Autodesk Fusion 360 part; units mm, degrees
(part 5 of 5)
sketch "草图7" plane through (0, 0, 4.4) normal (0, 0, 1) x (1, 0, 0) in component "03_可换镜像凹纹压片"
  line L0 (-23.5783, -0.5788) -> (-23.3448, -1.1469)
  line L1 (-23.3448, -1.1469) -> (-22.9926, -1.696)
  line L2 (-22.9926, -1.696) -> (-22.5708, -2.223)
  line L3 (-22.5708, -2.223) -> (-22.1372, -2.7304)
  line L4 (-22.1372, -2.7304) -> (-21.7491, -3.2262)
  line L5 (-21.7491, -3.2262) -> (-21.454, -3.7226)
  line L6 (-21.454, -3.7226) -> (-21.283, -4.2335)
  line L7 (-21.283, -4.2335) -> (-21.2455, -4.7708)
  line L8 (-21.2455, -4.7708) -> (-21.3281, -5.3424)
  line L9 (-21.3281, -5.3424) -> (-21.497, -5.949)
  line L10 (-21.497, -5.949) -> (-21.7034, -6.5837)
  line L11 (-21.7034, -6.5837) -> (-21.8914, -7.2319)
  line L12 (-21.8914, -7.2319) -> (-22.0067, -7.8741)
  line L13 (-22.0067, -7.8741) -> (-22.005, -8.4883)
  line L14 (-22.005, -8.4883) -> (-21.859, -9.0543)
  line L15 (-21.859, -9.0543) -> (-21.562, -9.5578)
  line L16 (-21.562, -9.5578) -> (-21.1289, -9.9932)
  line L17 (-21.1289, -9.9932) -> (-20.5933, -10.3658)
  line L18 (-20.5933, -10.3658) -> (-20.002, -10.6913)
  line L19 (-20.002, -10.6913) -> (-19.4073, -10.9941)
  line L20 (-19.4073, -10.9941) -> (-18.8589, -11.3036)
  line L21 (-18.8589, -11.3036) -> (-18.3963, -11.6494)
  line L22 (-18.3963, -11.6494) -> (-18.0429, -12.0559)
  line L23 (-18.0429, -12.0559) -> (-17.8026, -12.538)
  line L24 (-17.8026, -12.538) -> (-17.6602, -13.0977)
  line L25 (-17.6602, -13.0977) -> (-17.584, -13.7227)
  line L26 (-17.584, -13.7227) -> (-17.5319, -14.388)
  line L27 (-17.5319, -14.388) -> (-17.4575, -15.0589)
  line L28 (-17.4575, -15.0589) -> (-17.3182, -15.6963)
  line L29 (-17.3182, -15.6963) -> (-17.0817, -16.2631)
  line L30 (-17.0817, -16.2631) -> (-16.7301, -16.7301)
  line L31 (-16.7301, -16.7301) -> (-16.2631, -17.0817)
  line L32 (-16.2631, -17.0817) -> (-15.6963, -17.3182)
  line L33 (-15.6963, -17.3182) -> (-15.0589, -17.4575)
  line L34 (-15.0589, -17.4575) -> (-14.388, -17.5319)
  line L35 (-14.388, -17.5319) -> (-13.7227, -17.584)
  line L36 (-13.7227, -17.584) -> (-13.0977, -17.6602)
  line L37 (-13.0977, -17.6602) -> (-12.538, -17.8026)
  line L38 (-12.538, -17.8026) -> (-12.0559, -18.0429)
  line L39 (-12.0559, -18.0429) -> (-11.6494, -18.3963)
  line L40 (-11.6494, -18.3963) -> (-11.3036, -18.8589)
  line L41 (-11.3036, -18.8589) -> (-10.9941, -19.4073)
  line L42 (-10.9941, -19.4073) -> (-10.6913, -20.002)
  line L43 (-10.6913, -20.002) -> (-10.3658, -20.5933)
  line L44 (-10.3658, -20.5933) -> (-9.9932, -21.1289)
  line L45 (-9.9932, -21.1289) -> (-9.5578, -21.562)
  line L46 (-9.5578, -21.562) -> (-9.0543, -21.859)
  line L47 (-9.0543, -21.859) -> (-8.4883, -22.005)
  line L48 (-8.4883, -22.005) -> (-7.8741, -22.0067)
  line L49 (-7.8741, -22.0067) -> (-7.2319, -21.8914)
  line L50 (-7.2319, -21.8914) -> (-6.5837, -21.7034)
  line L51 (-6.5837, -21.7034) -> (-5.949, -21.497)
  line L52 (-5.949, -21.497) -> (-5.3424, -21.3281)
  line L53 (-5.3424, -21.3281) -> (-4.7708, -21.2455)
  line L54 (-4.7708, -21.2455) -> (-4.2335, -21.283)
  line L55 (-4.2335, -21.283) -> (-3.7226, -21.454)
  line L56 (-3.7226, -21.454) -> (-3.2262, -21.7491)
  line L57 (-3.2262, -21.7491) -> (-2.7304, -22.1372)
  line L58 (-2.7304, -22.1372) -> (-2.223, -22.5708)
  line L59 (-2.223, -22.5708) -> (-1.696, -22.9926)
  line L60 (-1.696, -22.9926) -> (-1.1469, -23.3448)
  line L61 (-1.1469, -23.3448) -> (-0.5788, -23.5783)
  line L62 (-0.5788, -23.5783) -> (0, -23.66)
  line L63 (0, -23.66) -> (0.5788, -23.5783)
  line L64 (0.5788, -23.5783) -> (1.1469, -23.3448)
  line L65 (1.1469, -23.3448) -> (1.696, -22.9926)
  line L66 (1.696, -22.9926) -> (2.223, -22.5708)
  line L67 (2.223, -22.5708) -> (2.7304, -22.1372)
  line L68 (2.7304, -22.1372) -> (3.2262, -21.7491)
  line L69 (3.2262, -21.7491) -> (3.7226, -21.454)
  line L70 (3.7226, -21.454) -> (4.2335, -21.283)
  line L71 (4.2335, -21.283) -> (4.7708, -21.2455)
  line L72 (4.7708, -21.2455) -> (5.3424, -21.3281)
  line L73 (5.3424, -21.3281) -> (5.949, -21.497)
  line L74 (5.949, -21.497) -> (6.5837, -21.7034)
  line L75 (6.5837, -21.7034) -> (7.2319, -21.8914)
  line L76 (7.2319, -21.8914) -> (7.8741, -22.0067)
  line L77 (7.8741, -22.0067) -> (8.4883, -22.005)
  line L78 (8.4883, -22.005) -> (9.0543, -21.859)
  line L79 (9.0543, -21.859) -> (9.5578, -21.562)
  line L80 (9.5578, -21.562) -> (9.9932, -21.1289)
  line L81 (9.9932, -21.1289) -> (10.3658, -20.5933)
  line L82 (10.3658, -20.5933) -> (10.6913, -20.002)
  line L83 (10.6913, -20.002) -> (10.9941, -19.4073)
  line L84 (10.9941, -19.4073) -> (11.3036, -18.8589)
  line L85 (11.3036, -18.8589) -> (11.6494, -18.3963)
  line L86 (11.6494, -18.3963) -> (12.0559, -18.0429)
  line L87 (12.0559, -18.0429) -> (12.538, -17.8026)
  line L88 (12.538, -17.8026) -> (13.0977, -17.6602)
  line L89 (13.0977, -17.6602) -> (13.7227, -17.584)
  line L90 (13.7227, -17.584) -> (14.388, -17.5319)
  line L91 (14.388, -17.5319) -> (15.0589, -17.4575)
  line L92 (15.0589, -17.4575) -> (15.6963, -17.3182)
  line L93 (15.6963, -17.3182) -> (16.2631, -17.0817)
  line L94 (16.2631, -17.0817) -> (16.7301, -16.7301)
  line L95 (16.7301, -16.7301) -> (17.0817, -16.2631)
  line L96 (17.0817, -16.2631) -> (17.3182, -15.6963)
  line L97 (17.3182, -15.6963) -> (17.4575, -15.0589)
  line L98 (17.4575, -15.0589) -> (17.5319, -14.388)
  line L99 (17.5319, -14.388) -> (17.584, -13.7227)
  line L100 (17.584, -13.7227) -> (17.6602, -13.0977)
  line L101 (17.6602, -13.0977) -> (17.8026, -12.538)
  line L102 (17.8026, -12.538) -> (18.0429, -12.0559)
  line L103 (18.0429, -12.0559) -> (18.3963, -11.6494)
  line L104 (18.3963, -11.6494) -> (18.8589, -11.3036)
  line L105 (18.8589, -11.3036) -> (19.4073, -10.9941)
  line L106 (19.4073, -10.9941) -> (20.002, -10.6913)
  line L107 (20.002, -10.6913) -> (20.5933, -10.3658)
  line L108 (20.5933, -10.3658) -> (21.1289, -9.9932)
  line L109 (21.1289, -9.9932) -> (21.562, -9.5578)
  line L110 (21.562, -9.5578) -> (21.859, -9.0543)
  line L111 (21.859, -9.0543) -> (22.005, -8.4883)
  line L112 (22.005, -8.4883) -> (22.0067, -7.8741)
  line L113 (22.0067, -7.8741) -> (21.8914, -7.2319)
  line L114 (21.8914, -7.2319) -> (21.7034, -6.5837)
  line L115 (21.7034, -6.5837) -> (21.497, -5.949)
  line L116 (21.497, -5.949) -> (21.3281, -5.3424)
  line L117 (21.3281, -5.3424) -> (21.2455, -4.7708)
  line L118 (21.2455, -4.7708) -> (21.283, -4.2335)
  line L119 (21.283, -4.2335) -> (21.454, -3.7226)
  line L120 (21.454, -3.7226) -> (21.7491, -3.2262)
  line L121 (21.7491, -3.2262) -> (22.1372, -2.7304)
  line L122 (22.1372, -2.7304) -> (22.5708, -2.223)
  line L123 (22.5708, -2.223) -> (22.9926, -1.696)
  line L124 (22.9926, -1.696) -> (23.3448, -1.1469)
  line L125 (23.3448, -1.1469) -> (23.5783, -0.5788)
  line L126 (23.5783, -0.5788) -> (23.66, 0)
  line L127 (23.66, 0) -> (23.5783, 0.5788)
  line L128 (23.5783, 0.5788) -> (23.3448, 1.1469)
  line L129 (23.3448, 1.1469) -> (22.9926, 1.696)
  line L130 (22.9926, 1.696) -> (22.5708, 2.223)
  line L131 (22.5708, 2.223) -> (22.1372, 2.7304)
  line L132 (22.1372, 2.7304) -> (21.7491, 3.2262)
  line L133 (21.7491, 3.2262) -> (21.454, 3.7226)
  line L134 (21.454, 3.7226) -> (21.283, 4.2335)
  line L135 (21.283, 4.2335) -> (21.2455, 4.7708)
  line L136 (21.2455, 4.7708) -> (21.3281, 5.3424)
  line L137 (21.3281, 5.3424) -> (21.497, 5.949)
  line L138 (21.497, 5.949) -> (21.7034, 6.5837)
  line L139 (21.7034, 6.5837) -> (21.8914, 7.2319)
  line L140 (21.8914, 7.2319) -> (22.0067, 7.8741)
  line L141 (22.0067, 7.8741) -> (22.005, 8.4883)
  line L142 (22.005, 8.4883) -> (21.859, 9.0543)
  line L143 (21.859, 9.0543) -> (21.562, 9.5578)
  line L144 (21.562, 9.5578) -> (21.1289, 9.9932)
  line L145 (21.1289, 9.9932) -> (20.5933, 10.3658)
  line L146 (20.5933, 10.3658) -> (20.002, 10.6913)
  line L147 (20.002, 10.6913) -> (19.4073, 10.9941)
  line L148 (19.4073, 10.9941) -> (18.8589, 11.3036)
  line L149 (18.8589, 11.3036) -> (18.3963, 11.6494)
  line L150 (18.3963, 11.6494) -> (18.0429, 12.0559)
  line L151 (18.0429, 12.0559) -> (17.8026, 12.538)
  line L152 (17.8026, 12.538) -> (17.6602, 13.0977)
  line L153 (17.6602, 13.0977) -> (17.584, 13.7227)
  line L154 (17.584, 13.7227) -> (17.5319, 14.388)
  line L155 (17.5319, 14.388) -> (17.4575, 15.0589)
  line L156 (17.4575, 15.0589) -> (17.3182, 15.6963)
  line L157 (17.3182, 15.6963) -> (17.0817, 16.2631)
  line L158 (17.0817, 16.2631) -> (16.7301, 16.7301)
  line L159 (16.7301, 16.7301) -> (16.2631, 17.0817)
  line L160 (16.2631, 17.0817) -> (15.6963, 17.3182)
  line L161 (15.6963, 17.3182) -> (15.0589, 17.4575)
  line L162 (15.0589, 17.4575) -> (14.388, 17.5319)
  line L163 (14.388, 17.5319) -> (13.7227, 17.584)
  line L164 (13.7227, 17.584) -> (13.0977, 17.6602)
  line L165 (13.0977, 17.6602) -> (12.538, 17.8026)
  line L166 (12.538, 17.8026) -> (12.0559, 18.0429)
  line L167 (12.0559, 18.0429) -> (11.6494, 18.3963)
  line L168 (11.6494, 18.3963) -> (11.3036, 18.8589)
  line L169 (11.3036, 18.8589) -> (10.9941, 19.4073)
  line L170 (10.9941, 19.4073) -> (10.6913, 20.002)
  line L171 (10.6913, 20.002) -> (10.3658, 20.5933)
  line L172 (10.3658, 20.5933) -> (9.9932, 21.1289)
  line L173 (9.9932, 21.1289) -> (9.5578, 21.562)
  line L174 (9.5578, 21.562) -> (9.0543, 21.859)
  line L175 (9.0543, 21.859) -> (8.4883, 22.005)
  line L176 (8.4883, 22.005) -> (7.8741, 22.0067)
  line L177 (7.8741, 22.0067) -> (7.2319, 21.8914)
  line L178 (7.2319, 21.8914) -> (6.5837, 21.7034)
  line L179 (6.5837, 21.7034) -> (5.949, 21.497)
  line L180 (5.949, 21.497) -> (5.3424, 21.3281)
  line L181 (5.3424, 21.3281) -> (4.7708, 21.2455)
  line L182 (4.7708, 21.2455) -> (4.2335, 21.283)
  line L183 (4.2335, 21.283) -> (3.7226, 21.454)
  line L184 (3.7226, 21.454) -> (3.2262, 21.7491)
  line L185 (3.2262, 21.7491) -> (2.7304, 22.1372)
  line L186 (2.7304, 22.1372) -> (2.223, 22.5708)
  line L187 (2.223, 22.5708) -> (1.696, 22.9926)
  line L188 (1.696, 22.9926) -> (1.1469, 23.3448)
  line L189 (1.1469, 23.3448) -> (0.5788, 23.5783)
  line L190 (0.5788, 23.5783) -> (0, 23.66)
  line L191 (0, 23.66) -> (-0.5788, 23.5783)
  line L192 (-0.5788, 23.5783) -> (-1.1469, 23.3448)
  line L193 (-1.1469, 23.3448) -> (-1.696, 22.9926)
  line L194 (-1.696, 22.9926) -> (-2.223, 22.5708)
  line L195 (-2.223, 22.5708) -> (-2.7304, 22.1372)
  line L196 (-2.7304, 22.1372) -> (-3.2262, 21.7491)
  line L197 (-3.2262, 21.7491) -> (-3.7226, 21.454)
  line L198 (-3.7226, 21.454) -> (-4.2335, 21.283)
  line L199 (-4.2335, 21.283) -> (-4.7708, 21.2455)
  line L200 (-4.7708, 21.2455) -> (-5.3424, 21.3281)
  line L201 (-5.3424, 21.3281) -> (-5.949, 21.497)
  line L202 (-5.949, 21.497) -> (-6.5837, 21.7034)
  line L203 (-6.5837, 21.7034) -> (-7.2319, 21.8914)
  line L204 (-7.2319, 21.8914) -> (-7.8741, 22.0067)
  line L205 (-7.8741, 22.0067) -> (-8.4883, 22.005)
  line L206 (-8.4883, 22.005) -> (-9.0543, 21.859)
  line L207 (-9.0543, 21.859) -> (-9.5578, 21.562)
  line L208 (-9.5578, 21.562) -> (-9.9932, 21.1289)
  line L209 (-9.9932, 21.1289) -> (-10.3658, 20.5933)
  line L210 (-10.3658, 20.5933) -> (-10.6913, 20.002)
  line L211 (-10.6913, 20.002) -> (-10.9941, 19.4073)
  line L212 (-10.9941, 19.4073) -> (-11.3036, 18.8589)
  line L213 (-11.3036, 18.8589) -> (-11.6494, 18.3963)
  line L214 (-11.6494, 18.3963) -> (-12.0559, 18.0429)
  line L215 (-12.0559, 18.0429) -> (-12.538, 17.8026)
  line L216 (-12.538, 17.8026) -> (-13.0977, 17.6602)
  line L217 (-13.0977, 17.6602) -> (-13.7227, 17.584)
  line L218 (-13.7227, 17.584) -> (-14.388, 17.5319)
  line L219 (-14.388, 17.5319) -> (-15.0589, 17.4575)
  line L220 (-15.0589, 17.4575) -> (-15.6963, 17.3182)
  line L221 (-15.6963, 17.3182) -> (-16.2631, 17.0817)
  line L222 (-16.2631, 17.0817) -> (-16.7301, 16.7301)
  line L223 (-16.7301, 16.7301) -> (-17.0817, 16.2631)
  line L224 (-17.0817, 16.2631) -> (-17.3182, 15.6963)
  line L225 (-17.3182, 15.6963) -> (-17.4575, 15.0589)
  line L226 (-17.4575, 15.0589) -> (-17.5319, 14.388)
  line L227 (-17.5319, 14.388) -> (-17.584, 13.7227)
  line L228 (-17.584, 13.7227) -> (-17.6602, 13.0977)
  line L229 (-17.6602, 13.0977) -> (-17.8026, 12.538)
  line L230 (-17.8026, 12.538) -> (-18.0429, 12.0559)
  line L231 (-18.0429, 12.0559) -> (-18.3963, 11.6494)
  line L232 (-18.3963, 11.6494) -> (-18.8589, 11.3036)
  line L233 (-18.8589, 11.3036) -> (-19.4073, 10.9941)
  line L234 (-19.4073, 10.9941) -> (-20.002, 10.6913)
  line L235 (-20.002, 10.6913) -> (-20.5933, 10.3658)
  line L236 (-20.5933, 10.3658) -> (-21.1289, 9.9932)
  line L237 (-21.1289, 9.9932) -> (-21.562, 9.5578)
  line L238 (-21.562, 9.5578) -> (-21.859, 9.0543)
  line L239 (-21.859, 9.0543) -> (-22.005, 8.4883)
  line L240 (-22.005, 8.4883) -> (-22.0067, 7.8741)
  line L241 (-22.0067, 7.8741) -> (-21.8914, 7.2319)
  line L242 (-21.8914, 7.2319) -> (-21.7034, 6.5837)
  line L243 (-21.7034, 6.5837) -> (-21.497, 5.949)
  line L244 (-21.497, 5.949) -> (-21.3281, 5.3424)
  line L245 (-21.3281, 5.3424) -> (-21.2455, 4.7708)
  line L246 (-21.2455, 4.7708) -> (-21.283, 4.2335)
  line L247 (-21.283, 4.2335) -> (-21.454, 3.7226)
  line L248 (-21.454, 3.7226) -> (-21.7491, 3.2262)
  line L249 (-21.7491, 3.2262) -> (-22.1372, 2.7304)
  line L250 (-22.1372, 2.7304) -> (-22.5708, 2.223)
  line L251 (-22.5708, 2.223) -> (-22.9926, 1.696)
  line L252 (-22.9926, 1.696) -> (-23.3448, 1.1469)
  line L253 (-23.3448, 1.1469) -> (-23.5783, 0.5788)
  line L254 (-23.5783, 0.5788) -> (-23.66, 0)
  line L255 (-23.66, 0) -> (-23.5783, -0.5788)
  line L256 (-22.7785, 0.5592) -> (-22.5458, 1.1076)
  line L257 (-22.5458, 1.1076) -> (-22.1947, 1.6372)
  line L258 (-22.1947, 1.6372) -> (-21.7746, 2.1446)
  line L259 (-21.7746, 2.1446) -> (-21.3432, 2.6324)
  line L260 (-21.3432, 2.6324) -> (-20.9577, 3.1088)
  line L261 (-20.9577, 3.1088) -> (-20.6658, 3.5859)
  line L262 (-20.6658, 3.5859) -> (-20.4984, 4.0774)
  line L263 (-20.4984, 4.0774) -> (-20.465, 4.5956)
  line L264 (-20.465, 4.5956) -> (-20.5521, 5.148)
  line L265 (-20.5521, 5.148) -> (-20.726, 5.7356)
  line L266 (-20.726, 5.7356) -> (-20.9379, 6.3514)
  line L267 (-20.9379, 6.3514) -> (-21.1318, 6.981)
  line L268 (-21.1318, 6.981) -> (-21.2534, 7.6046)
  line L269 (-21.2534, 7.6046) -> (-21.2586, 8.2004)
  line L270 (-21.2586, 8.2004) -> (-21.1199, 8.7481)
  line L271 (-21.1199, 8.7481) -> (-20.8306, 9.2336)
  line L272 (-20.8306, 9.2336) -> (-20.4057, 9.6512)
  line L273 (-20.4057, 9.6512) -> (-19.8787, 10.0061)
  line L274 (-19.8787, 10.0061) -> (-19.2964, 10.3142)
  line L275 (-19.2964, 10.3142) -> (-18.7112, 10.5998)
  line L276 (-18.7112, 10.5998) -> (-18.1727, 10.8923)
  line L277 (-18.1727, 10.8923) -> (-17.7205, 11.2214)
  line L278 (-17.7205, 11.2214) -> (-17.3777, 11.6114)
  line L279 (-17.3777, 11.6114) -> (-17.1485, 12.0773)
  line L280 (-17.1485, 12.0773) -> (-17.0176, 12.6211)
  line L281 (-17.0176, 12.6211) -> (-16.9534, 13.2305)
  line L282 (-16.9534, 13.2305) -> (-16.9135, 13.8805)
  line L283 (-16.9135, 13.8805) -> (-16.8517, 14.5364)
  line L284 (-16.8517, 14.5364) -> (-16.7255, 15.1591)
  line L285 (-16.7255, 15.1591) -> (-16.5023, 15.7115)
  line L286 (-16.5023, 15.7115) -> (-16.1645, 16.1645)
  line L287 (-16.1645, 16.1645) -> (-15.7115, 16.5023)
  line L288 (-15.7115, 16.5023) -> (-15.1591, 16.7255)
  line L289 (-15.1591, 16.7255) -> (-14.5364, 16.8517)
  line L290 (-14.5364, 16.8517) -> (-13.8805, 16.9135)
  line L291 (-13.8805, 16.9135) -> (-13.2305, 16.9534)
  line L292 (-13.2305, 16.9534) -> (-12.6211, 17.0176)
  line L293 (-12.6211, 17.0176) -> (-12.0773, 17.1485)
  line L294 (-12.0773, 17.1485) -> (-11.6114, 17.3777)
  line L295 (-11.6114, 17.3777) -> (-11.2214, 17.7205)
  line L296 (-11.2214, 17.7205) -> (-10.8923, 18.1727)
  line L297 (-10.8923, 18.1727) -> (-10.5998, 18.7112)
  line L298 (-10.5998, 18.7112) -> (-10.3142, 19.2964)
  line L299 (-10.3142, 19.2964) -> (-10.0061, 19.8787)
  line L300 (-10.0061, 19.8787) -> (-9.6512, 20.4057)
  line L301 (-9.6512, 20.4057) -> (-9.2336, 20.8306)
  line L302 (-9.2336, 20.8306) -> (-8.7481, 21.1199)
  line L303 (-8.7481, 21.1199) -> (-8.2004, 21.2586)
  line L304 (-8.2004, 21.2586) -> (-7.6046, 21.2534)
  line L305 (-7.6046, 21.2534) -> (-6.981, 21.1318)
  line L306 (-6.981, 21.1318) -> (-6.3514, 20.9379)
  line L307 (-6.3514, 20.9379) -> (-5.7356, 20.726)
  line L308 (-5.7356, 20.726) -> (-5.148, 20.5521)
  line L309 (-5.148, 20.5521) -> (-4.5956, 20.465)
  line L310 (-4.5956, 20.465) -> (-4.0774, 20.4984)
  line L311 (-4.0774, 20.4984) -> (-3.5859, 20.6658)
  line L312 (-3.5859, 20.6658) -> (-3.1088, 20.9577)
  line L313 (-3.1088, 20.9577) -> (-2.6324, 21.3432)
  line L314 (-2.6324, 21.3432) -> (-2.1446, 21.7746)
  line L315 (-2.1446, 21.7746) -> (-1.6372, 22.1947)
  line L316 (-1.6372, 22.1947) -> (-1.1076, 22.5458)
  line L317 (-1.1076, 22.5458) -> (-0.5592, 22.7785)
  line L318 (-0.5592, 22.7785) -> (0, 22.86)
  line L319 (0, 22.86) -> (0.5592, 22.7785)
  line L320 (0.5592, 22.7785) -> (1.1076, 22.5458)
  line L321 (1.1076, 22.5458) -> (1.6372, 22.1947)
  line L322 (1.6372, 22.1947) -> (2.1446, 21.7746)
  line L323 (2.1446, 21.7746) -> (2.6324, 21.3432)
  line L324 (2.6324, 21.3432) -> (3.1088, 20.9577)
  line L325 (3.1088, 20.9577) -> (3.5859, 20.6658)
  line L326 (3.5859, 20.6658) -> (4.0774, 20.4984)
  line L327 (4.0774, 20.4984) -> (4.5956, 20.465)
  line L328 (4.5956, 20.465) -> (5.148, 20.5521)
  line L329 (5.148, 20.5521) -> (5.7356, 20.726)
  line L330 (5.7356, 20.726) -> (6.3514, 20.9379)
  line L331 (6.3514, 20.9379) -> (6.981, 21.1318)
  line L332 (6.981, 21.1318) -> (7.6046, 21.2534)
  line L333 (7.6046, 21.2534) -> (8.2004, 21.2586)
  line L334 (8.2004, 21.2586) -> (8.7481, 21.1199)
  line L335 (8.7481, 21.1199) -> (9.2336, 20.8306)
  line L336 (9.2336, 20.8306) -> (9.6512, 20.4057)
  line L337 (9.6512, 20.4057) -> (10.0061, 19.8787)
  line L338 (10.0061, 19.8787) -> (10.3142, 19.2964)
  line L339 (10.3142, 19.2964) -> (10.5998, 18.7112)
  line L340 (10.5998, 18.7112) -> (10.8923, 18.1727)
  line L341 (10.8923, 18.1727) -> (11.2214, 17.7205)
  line L342 (11.2214, 17.7205) -> (11.6114, 17.3777)
  line L343 (11.6114, 17.3777) -> (12.0773, 17.1485)
  line L344 (12.0773, 17.1485) -> (12.6211, 17.0176)
  line L345 (12.6211, 17.0176) -> (13.2305, 16.9534)
  line L346 (13.2305, 16.9534) -> (13.8805, 16.9135)
  line L347 (13.8805, 16.9135) -> (14.5364, 16.8517)
  line L348 (14.5364, 16.8517) -> (15.1591, 16.7255)
  line L349 (15.1591, 16.7255) -> (15.7115, 16.5023)
  line L350 (15.7115, 16.5023) -> (16.1645, 16.1645)
  line L351 (16.1645, 16.1645) -> (16.5023, 15.7115)
  line L352 (16.5023, 15.7115) -> (16.7255, 15.1591)
  line L353 (16.7255, 15.1591) -> (16.8517, 14.5364)
  line L354 (16.8517, 14.5364) -> (16.9135, 13.8805)
  line L355 (16.9135, 13.8805) -> (16.9534, 13.2305)
  line L356 (16.9534, 13.2305) -> (17.0176, 12.6211)
  line L357 (17.0176, 12.6211) -> (17.1485, 12.0773)
  line L358 (17.1485, 12.0773) -> (17.3777, 11.6114)
  line L359 (17.3777, 11.6114) -> (17.7205, 11.2214)
  line L360 (17.7205, 11.2214) -> (18.1727, 10.8923)
  line L361 (18.1727, 10.8923) -> (18.7112, 10.5998)
  line L362 (18.7112, 10.5998) -> (19.2964, 10.3142)
  line L363 (19.2964, 10.3142) -> (19.8787, 10.0061)
  line L364 (19.8787, 10.0061) -> (20.4057, 9.6512)
  line L365 (20.4057, 9.6512) -> (20.8306, 9.2336)
  line L366 (20.8306, 9.2336) -> (21.1199, 8.7481)
  line L367 (21.1199, 8.7481) -> (21.2586, 8.2004)
  line L368 (21.2586, 8.2004) -> (21.2534, 7.6046)
  line L369 (21.2534, 7.6046) -> (21.1318, 6.981)
  line L370 (21.1318, 6.981) -> (20.9379, 6.3514)
  line L371 (20.9379, 6.3514) -> (20.726, 5.7356)
  line L372 (20.726, 5.7356) -> (20.5521, 5.148)
  line L373 (20.5521, 5.148) -> (20.465, 4.5956)
  line L374 (20.465, 4.5956) -> (20.4984, 4.0774)
  line L375 (20.4984, 4.0774) -> (20.6658, 3.5859)
  line L376 (20.6658, 3.5859) -> (20.9577, 3.1088)
  line L377 (20.9577, 3.1088) -> (21.3432, 2.6324)
  line L378 (21.3432, 2.6324) -> (21.7746, 2.1446)
  line L379 (21.7746, 2.1446) -> (22.1947, 1.6372)
  line L380 (22.1947, 1.6372) -> (22.5458, 1.1076)
  line L381 (22.5458, 1.1076) -> (22.7785, 0.5592)
  line L382 (22.7785, 0.5592) -> (22.86, 0)
  line L383 (22.86, 0) -> (22.7785, -0.5592)
  line L384 (22.7785, -0.5592) -> (22.5458, -1.1076)
  line L385 (22.5458, -1.1076) -> (22.1947, -1.6372)
  line L386 (22.1947, -1.6372) -> (21.7746, -2.1446)
  line L387 (21.7746, -2.1446) -> (21.3432, -2.6324)
  line L388 (21.3432, -2.6324) -> (20.9577, -3.1088)
  line L389 (20.9577, -3.1088) -> (20.6658, -3.5859)
  line L390 (20.6658, -3.5859) -> (20.4984, -4.0774)
  line L391 (20.4984, -4.0774) -> (20.465, -4.5956)
  line L392 (20.465, -4.5956) -> (20.5521, -5.148)
  line L393 (20.5521, -5.148) -> (20.726, -5.7356)
  line L394 (20.726, -5.7356) -> (20.9379, -6.3514)
  line L395 (20.9379, -6.3514) -> (21.1318, -6.981)
  line L396 (21.1318, -6.981) -> (21.2534, -7.6046)
  line L397 (21.2534, -7.6046) -> (21.2586, -8.2004)
  line L398 (21.2586, -8.2004) -> (21.1199, -8.7481)
  line L399 (21.1199, -8.7481) -> (20.8306, -9.2336)
  line L400 (20.8306, -9.2336) -> (20.4057, -9.6512)
  line L401 (20.4057, -9.6512) -> (19.8787, -10.0061)
  line L402 (19.8787, -10.0061) -> (19.2964, -10.3142)
  line L403 (19.2964, -10.3142) -> (18.7112, -10.5998)
  line L404 (18.7112, -10.5998) -> (18.1727, -10.8923)
  line L405 (18.1727, -10.8923) -> (17.7205, -11.2214)
  line L406 (17.7205, -11.2214) -> (17.3777, -11.6114)
  line L407 (17.3777, -11.6114) -> (17.1485, -12.0773)
  line L408 (17.1485, -12.0773) -> (17.0176, -12.6211)
  line L409 (17.0176, -12.6211) -> (16.9534, -13.2305)
  line L410 (16.9534, -13.2305) -> (16.9135, -13.8805)
  line L411 (16.9135, -13.8805) -> (16.8517, -14.5364)
  line L412 (16.8517, -14.5364) -> (16.7255, -15.1591)
  line L413 (16.7255, -15.1591) -> (16.5023, -15.7115)
  line L414 (16.5023, -15.7115) -> (16.1645, -16.1645)
  line L415 (16.1645, -16.1645) -> (15.7115, -16.5023)
  line L416 (15.7115, -16.5023) -> (15.1591, -16.7255)
  line L417 (15.1591, -16.7255) -> (14.5364, -16.8517)
  line L418 (14.5364, -16.8517) -> (13.8805, -16.9135)
  line L419 (13.8805, -16.9135) -> (13.2305, -16.9534)
  line L420 (13.2305, -16.9534) -> (12.6211, -17.0176)
  line L421 (12.6211, -17.0176) -> (12.0773, -17.1485)
  line L422 (12.0773, -17.1485) -> (11.6114, -17.3777)
  line L423 (11.6114, -17.3777) -> (11.2214, -17.7205)
  line L424 (11.2214, -17.7205) -> (10.8923, -18.1727)
  line L425 (10.8923, -18.1727) -> (10.5998, -18.7112)
  line L426 (10.5998, -18.7112) -> (10.3142, -19.2964)
  line L427 (10.3142, -19.2964) -> (10.0061, -19.8787)
  line L428 (10.0061, -19.8787) -> (9.6512, -20.4057)
  line L429 (9.6512, -20.4057) -> (9.2336, -20.8306)
  line L430 (9.2336, -20.8306) -> (8.7481, -21.1199)
  line L431 (8.7481, -21.1199) -> (8.2004, -21.2586)
  line L432 (8.2004, -21.2586) -> (7.6046, -21.2534)
  line L433 (7.6046, -21.2534) -> (6.981, -21.1318)
  line L434 (6.981, -21.1318) -> (6.3514, -20.9379)
  line L435 (6.3514, -20.9379) -> (5.7356, -20.726)
  line L436 (5.7356, -20.726) -> (5.148, -20.5521)
  line L437 (5.148, -20.5521) -> (4.5956, -20.465)
  line L438 (4.5956, -20.465) -> (4.0774, -20.4984)
  line L439 (4.0774, -20.4984) -> (3.5859, -20.6658)
  line L440 (3.5859, -20.6658) -> (3.1088, -20.9577)
  line L441 (3.1088, -20.9577) -> (2.6324, -21.3432)
  line L442 (2.6324, -21.3432) -> (2.1446, -21.7746)
  line L443 (2.1446, -21.7746) -> (1.6372, -22.1947)
  line L444 (1.6372, -22.1947) -> (1.1076, -22.5458)
  line L445 (1.1076, -22.5458) -> (0.5592, -22.7785)
  line L446 (0.5592, -22.7785) -> (0, -22.86)
  line L447 (0, -22.86) -> (-0.5592, -22.7785)
  line L448 (-0.5592, -22.7785) -> (-1.1076, -22.5458)
  line L449 (-1.1076, -22.5458) -> (-1.6372, -22.1947)
  line L450 (-1.6372, -22.1947) -> (-2.1446, -21.7746)
  line L451 (-2.1446, -21.7746) -> (-2.6324, -21.3432)
  line L452 (-2.6324, -21.3432) -> (-3.1088, -20.9577)
  line L453 (-3.1088, -20.9577) -> (-3.5859, -20.6658)
  line L454 (-3.5859, -20.6658) -> (-4.0774, -20.4984)
  line L455 (-4.0774, -20.4984) -> (-4.5956, -20.465)
  line L456 (-4.5956, -20.465) -> (-5.148, -20.5521)
  line L457 (-5.148, -20.5521) -> (-5.7356, -20.726)
  line L458 (-5.7356, -20.726) -> (-6.3514, -20.9379)
  line L459 (-6.3514, -20.9379) -> (-6.981, -21.1318)
  line L460 (-6.981, -21.1318) -> (-7.6046, -21.2534)
  line L461 (-7.6046, -21.2534) -> (-8.2004, -21.2586)
  line L462 (-8.2004, -21.2586) -> (-8.7481, -21.1199)
  line L463 (-8.7481, -21.1199) -> (-9.2336, -20.8306)
  line L464 (-9.2336, -20.8306) -> (-9.6512, -20.4057)
  line L465 (-9.6512, -20.4057) -> (-10.0061, -19.8787)
  line L466 (-10.0061, -19.8787) -> (-10.3142, -19.2964)
  line L467 (-10.3142, -19.2964) -> (-10.5998, -18.7112)
  line L468 (-10.5998, -18.7112) -> (-10.8923, -18.1727)
  line L469 (-10.8923, -18.1727) -> (-11.2214, -17.7205)
  line L470 (-11.2214, -17.7205) -> (-11.6114, -17.3777)
  line L471 (-11.6114, -17.3777) -> (-12.0773, -17.1485)
  line L472 (-12.0773, -17.1485) -> (-12.6211, -17.0176)
  line L473 (-12.6211, -17.0176) -> (-13.2305, -16.9534)
  line L474 (-13.2305, -16.9534) -> (-13.8805, -16.9135)
  line L475 (-13.8805, -16.9135) -> (-14.5364, -16.8517)
  line L476 (-14.5364, -16.8517) -> (-15.1591, -16.7255)
  line L477 (-15.1591, -16.7255) -> (-15.7115, -16.5023)
  line L478 (-15.7115, -16.5023) -> (-16.1645, -16.1645)
  line L479 (-16.1645, -16.1645) -> (-16.5023, -15.7115)
  line L480 (-16.5023, -15.7115) -> (-16.7255, -15.1591)
  line L481 (-16.7255, -15.1591) -> (-16.8517, -14.5364)
  line L482 (-16.8517, -14.5364) -> (-16.9135, -13.8805)
  line L483 (-16.9135, -13.8805) -> (-16.9534, -13.2305)
  line L484 (-16.9534, -13.2305) -> (-17.0176, -12.6211)
  line L485 (-17.0176, -12.6211) -> (-17.1485, -12.0773)
  line L486 (-17.1485, -12.0773) -> (-17.3777, -11.6114)
  line L487 (-17.3777, -11.6114) -> (-17.7205, -11.2214)
  line L488 (-17.7205, -11.2214) -> (-18.1727, -10.8923)
  line L489 (-18.1727, -10.8923) -> (-18.7112, -10.5998)
  line L490 (-18.7112, -10.5998) -> (-19.2964, -10.3142)
  line L491 (-19.2964, -10.3142) -> (-19.8787, -10.0061)
  line L492 (-19.8787, -10.0061) -> (-20.4057, -9.6512)
  line L493 (-20.4057, -9.6512) -> (-20.8306, -9.2336)
  line L494 (-20.8306, -9.2336) -> (-21.1199, -8.7481)
  line L495 (-21.1199, -8.7481) -> (-21.2586, -8.2004)
  line L496 (-21.2586, -8.2004) -> (-21.2534, -7.6046)
  line L497 (-21.2534, -7.6046) -> (-21.1318, -6.981)
  line L498 (-21.1318, -6.981) -> (-20.9379, -6.3514)
  line L499 (-20.9379, -6.3514) -> (-20.726, -5.7356)
  line L500 (-20.726, -5.7356) -> (-20.5521, -5.148)
  line L501 (-20.5521, -5.148) -> (-20.465, -4.5956)
  line L502 (-20.465, -4.5956) -> (-20.4984, -4.0774)
  line L503 (-20.4984, -4.0774) -> (-20.6658, -3.5859)
  line L504 (-20.6658, -3.5859) -> (-20.9577, -3.1088)
  line L505 (-20.9577, -3.1088) -> (-21.3432, -2.6324)
  line L506 (-21.3432, -2.6324) -> (-21.7746, -2.1446)
  line L507 (-21.7746, -2.1446) -> (-22.1947, -1.6372)
  line L508 (-22.1947, -1.6372) -> (-22.5458, -1.1076)
  line L509 (-22.5458, -1.1076) -> (-22.7785, -0.5592)
  line L510 (-22.7785, -0.5592) -> (-22.86, 0)
  line L511 (-22.86, 0) -> (-22.7785, 0.5592)
extrude "镜像凹纹_004 (1)" cut sketch "草图7" along normal blind 1.63 bodies 3 in component "03_可换镜像凹纹压片"
ref_plane "工作平面7" through (0, 0, 4.4) normal (0, 0, 1) x (1, 0, 0) in component "03_可换镜像凹纹压片"
sketch "草图8" plane through (0, 0, 4.4) normal (0, 0, 1) x (1, 0, 0) in component "03_可换镜像凹纹压片"
  line L0 (7.4923, -7.7969) -> (7.7153, -7.2532)
  line L1 (7.7153, -7.2532) -> (7.6671, -7.0488)
  line L2 (7.6671, -7.0488) -> (4.0783, -7.1047)
  line L3 (4.0783, -7.1047) -> (3.99, -7.0357)
  line L4 (3.99, -7.0357) -> (4.2244, -6.6007)
  line L5 (4.2244, -6.6007) -> (4.5784, -5.187)
  line L6 (4.5784, -5.187) -> (5.4213, -3.6644)
  line L7 (5.4213, -3.6644) -> (5.4274, -3.4469)
  line L8 (5.4274, -3.4469) -> (5.2746, -3.2675)
  line L9 (5.2746, -3.2675) -> (5.0571, -3.2961)
  line L10 (5.0571, -3.2961) -> (3.8608, -3.9534)
  line L11 (3.8608, -3.9534) -> (3.1179, -4.5344)
  line L12 (3.1179, -4.5344) -> (2.7518, -4.9694)
  line L13 (2.7518, -4.9694) -> (2.6207, -5.2957)
  line L14 (2.6207, -5.2957) -> (2.6385, -5.9482)
  line L15 (2.6385, -5.9482) -> (2.9574, -6.6007)
  line L16 (2.9574, -6.6007) -> (3.4259, -7.0743)
  line L17 (3.4259, -7.0743) -> (1.2509, -7.1047)
  line L18 (1.2509, -7.1047) -> (1.1512, -7.0357)
  line L19 (1.1512, -7.0357) -> (1.186, -2.5769)
  line L20 (1.186, -2.5769) -> (5.4922, -2.5412)
  line L21 (5.4922, -2.5412) -> (6.2533, -2.6658)
  line L22 (6.2533, -2.6658) -> (6.6179, -1.9244)
  line L23 (6.6179, -1.9244) -> (1.2509, -1.9724)
  line L24 (1.2509, -1.9724) -> (1.1512, -1.8157)
  line L25 (1.1512, -1.8157) -> (1.1854, 0.5768)
  line L26 (1.1854, 0.5768) -> (3.6433, 0.6134)
  line L27 (3.6433, 0.6134) -> (4.5133, 0.5243)
  line L28 (4.5133, 0.5243) -> (4.7308, 0.9523)
  line L29 (4.7308, 0.9523) -> (6.2533, -0.0157)
  line L30 (6.2533, -0.0157) -> (8.1022, -0.9733)
  line L31 (8.1022, -0.9733) -> (8.3698, -0.5107)
  line L32 (8.3698, -0.5107) -> (6.0358, 1.1825)
  line L33 (6.0358, 1.1825) -> (3.9255, 3.1868)
  line L34 (3.9255, 3.1868) -> (2.4172, 5.2531)
  line L35 (2.4172, 5.2531) -> (1.0334, 7.797)
  line L36 (1.0334, 7.797) -> (-0.3803, 7.3551)
  line L37 (-0.3803, 7.3551) -> (-0.9904, 6.9931)
  line L38 (-0.9904, 6.9931) -> (-1.0645, 6.8843)
  line L39 (-1.0645, 6.8843) -> (-0.9439, 6.6668)
  line L40 (-0.9439, 6.6668) -> (-0.545, 6.4493)
  line L41 (-0.545, 6.4493) -> (-0.6879, 6.2318)
  line L42 (-0.6879, 6.2318) -> (-2.0116, 4.6652)
  line L43 (-2.0116, 4.6652) -> (-3.7517, 3.2684)
  line L44 (-3.7517, 3.2684) -> (-5.9266, 2.1644)
  line L45 (-5.9266, 2.1644) -> (-8.3192, 1.4998)
  line L46 (-8.3192, 1.4998) -> (-8.3699, 1.1206)
  line L47 (-8.3699, 1.1206) -> (-7.1229, 0.8094)
  line L48 (-7.1229, 0.8094) -> (-6.3617, 0.0877)
  line L49 (-6.3617, 0.0877) -> (-6.0353, 0.1076)
  line L50 (-6.0353, 0.1076) -> (-3.8603, 1.376)
  line L51 (-3.8603, 1.376) -> (-3.0657, 2.0993)
  line L52 (-3.0657, 2.0993) -> (-1.4406, 3.8393)
  line L53 (-1.4406, 3.8393) -> (-0.7726, 4.8181)
  line L54 (-0.7726, 4.8181) -> (-0.1628, 5.9808)
  line L55 (-0.1628, 5.9808) -> (-0.0074, 5.9056)
  line L56 (-0.0074, 5.9056) -> (2.0719, 3.2956)
  line L57 (2.0719, 3.2956) -> (3.3171, 2.0668)
  line L58 (3.3171, 2.0668) -> (4.235, 1.3381)
  line L59 (4.235, 1.3381) -> (3.8608, 1.245)
  line L60 (3.8608, 1.245) -> (-1.6853, 1.2503)
  line L61 (-1.6853, 1.2503) -> (-2.4466, 2.1387)
  line L62 (-2.4466, 2.1387) -> (-2.6641, 2.1849)
  line L63 (-2.6641, 2.1849) -> (-3.4254, 1.7351)
  line L64 (-3.4254, 1.7351) -> (-4.3447, 0.9031)
  line L65 (-4.3447, 0.9031) -> (-4.4041, 0.6711)
  line L66 (-4.4041, 0.6711) -> (-0.5692, 0.5768)
  line L67 (-0.5692, 0.5768) -> (-0.5564, -1.9244)
  line L68 (-0.5564, -1.9244) -> (-3.4254, -1.9724)
  line L69 (-3.4254, -1.9724) -> (-4.2954, -0.8934)
  line L70 (-4.2954, -0.8934) -> (-4.6217, -0.7662)
  line L71 (-4.6217, -0.7662) -> (-4.9479, -0.9294)
  line L72 (-4.9479, -0.9294) -> (-5.8179, -1.6727)
  line L73 (-5.8179, -1.6727) -> (-6.2626, -2.1419)
  line L74 (-6.2626, -2.1419) -> (-6.3447, -2.3594)
  line L75 (-6.3447, -2.3594) -> (-6.2528, -2.5175)
  line L76 (-6.2528, -2.5175) -> (-6.0353, -2.5396)
  line L77 (-6.0353, -2.5396) -> (-0.5978, -2.5488)
  line L78 (-0.5978, -2.5488) -> (-0.5488, -7.0357)
  line L79 (-0.5488, -7.0357) -> (-1.1416, -7.1047)
  line L80 (-1.1416, -7.1047) -> (-1.2503, -7.0319)
  line L81 (-1.2503, -7.0319) -> (-2.144, -5.2957)
  line L82 (-2.144, -5.2957) -> (-2.9622, -3.1207)
  line L83 (-2.9622, -3.1207) -> (-3.0992, -3.0665)
  line L84 (-3.0992, -3.0665) -> (-4.6217, -3.9513)
  line L85 (-4.6217, -3.9513) -> (-4.8782, -4.2082)
  line L86 (-4.8782, -4.2082) -> (-4.8831, -4.4257)
  line L87 (-4.8831, -4.4257) -> (-4.0779, -4.8219)
  line L88 (-4.0779, -4.8219) -> (-2.2291, -7.0743)
  line L89 (-2.2291, -7.0743) -> (-4.5128, -7.0841)
  line L90 (-4.5128, -7.0841) -> (-5.6004, -5.8104)
  line L91 (-5.6004, -5.8104) -> (-5.9266, -5.7943)
  line L92 (-5.9266, -5.7943) -> (-7.2448, -7.1444)
  line L93 (-7.2448, -7.1444) -> (-7.4922, -7.5794)
  line L94 (-7.4922, -7.5794) -> (-7.4326, -7.6882)
  line L95 (-7.4326, -7.6882) -> (-7.1229, -7.7561)
  line L96 (-7.1229, -7.7561) -> (6.9964, -7.7969)
  line L97 (6.9964, -7.7969) -> (7.4923, -7.7969)
extrude "镜像凹纹_005 (1)" cut sketch "草图8" along normal blind 1.63 bodies 3 in component "03_可换镜像凹纹压片"
sketch "草图1 (4)" plane through (0, 0, 0) normal (0, 0, 1) x (1, 0, 0) in component "04_螺纹推杆与手柄"
  circle A0 centre (0, 0) radius 6
extrude "导向推杆 (1)" add sketch "草图1 (4)" along normal blind 73.5 separate body makes body 4 in component "04_螺纹推杆与手柄"
ref_plane "工作平面1" through (0, 0, -10) normal (0, 0, 1) x (1, 0, 0) in component "04_螺纹推杆与手柄"
sketch "草图2 (4)" plane through (0, 0, -10) normal (0, 0, 1) x (1, 0, 0) in component "04_螺纹推杆与手柄"
  circle A0 centre (0, 0) radius 4
extrude "M8 连接螺柱 (1)" add sketch "草图2 (4)" along normal blind 10.03 bodies 4 in component "04_螺纹推杆与手柄"
thread "M8x1.25 外螺纹" "ISO Metric profile 8.0 M8x1.25 M8x1.25 6g" major diameter 7.866 minor diameter 6.4455 pitch 1.25 angle 60 modelled right hand crest width 0.1833 on face at (3.9801, 0.3983, -3.3333) crest through (3.933, 0, -10.3125) on bodies 4 in component "04_螺纹推杆与手柄"
ref_plane "工作平面2" through (0, 0, 73.47) normal (0, 0, 1) x (1, 0, 0) in component "04_螺纹推杆与手柄"
sketch "草图3 (4)" plane through (0, 0, 73.47) normal (0, 0, 1) x (1, 0, 0) in component "04_螺纹推杆与手柄"
  circle A0 centre (0, 0) radius 22
extrude "推压手柄 (1)" add sketch "草图3 (4)" along normal blind 7.03 bodies 4 in component "04_螺纹推杆与手柄"
component "02_模具外套筒" placed x (1, 0, 0) y (0, 1, 0) z (0, 0, 1) at (57.8, -57.8, 0)
component "03_可换镜像凹纹压片" placed x (1, 0, 0) y (0, 1, 0) z (0, 0, 1) at (-57.8, 57.8, 12)
component "04_螺纹推杆与手柄" placed x (1, 0, 0) y (0, 1, 0) z (0, 0, 1) at (57.8, 57.8, 10)
component "01_月饼_金_68mm" placed x (1, 0, 0) y (0, 1, 0) z (0, 0, 1) at (-57.8, -57.8, 0)
named bodies: "01_月饼_金_68mm", "02_模具外套筒", "03_可换镜像凹纹压片", "04_螺纹推杆与手柄"
